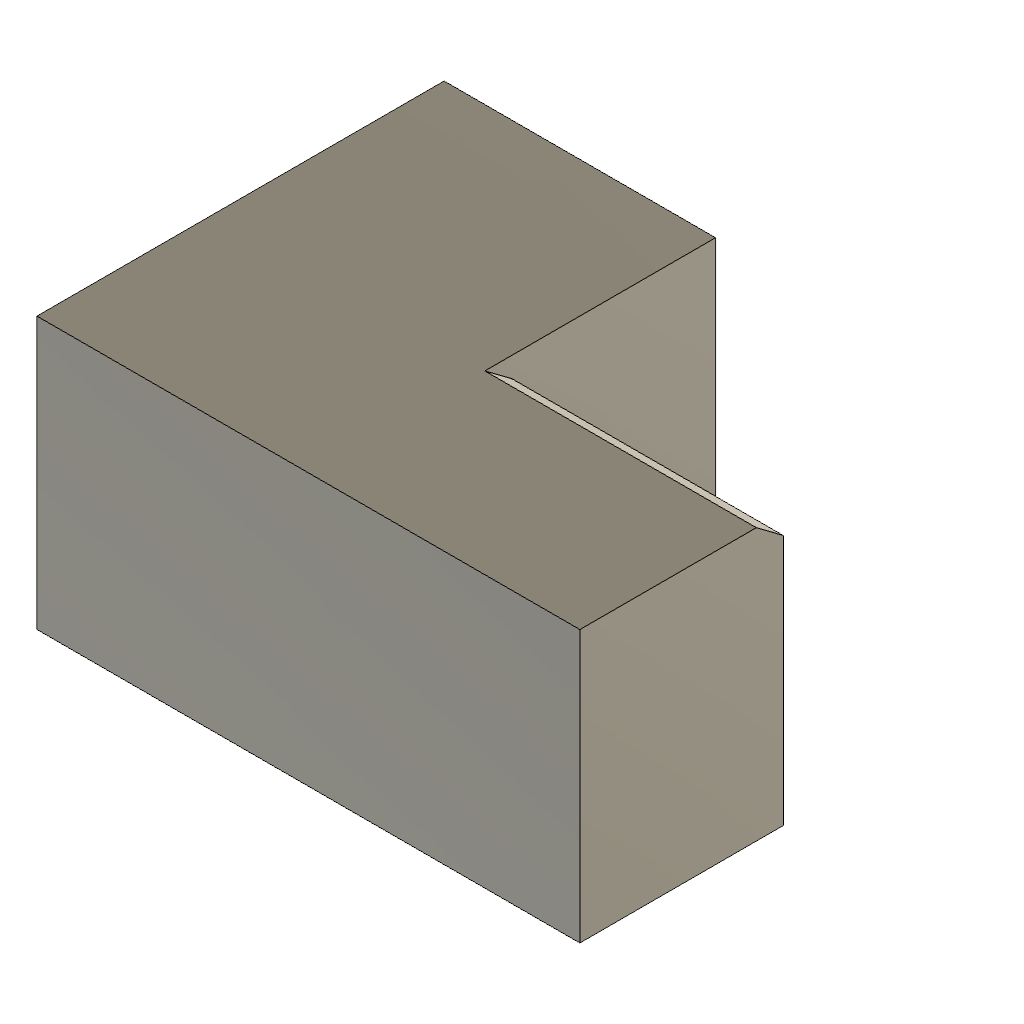
vendor_BevelStepTwo (Autodesk Fusion 360 design; units mm, degrees)
Autodesk Fusion 360 part; units mm, degrees
sketch "Step sketch" plane through (0, 0, 0) normal (0, 0, 1) x (1, 0, 0)
  line L0 (0, 0) -> (40, 0)
  line L1 (40, 0) -> (40, 15)
  line L2 (40, 15) -> (20, 15)
  line L3 (20, 15) -> (20, 30)
  line L4 (20, 30) -> (0, 30)
  line L5 (0, 30) -> (0, 0)
extrude "Step extrude" add sketch "Step sketch" along normal blind 20
chamfer "Step bevel" distance 2 distance2 1.5 1 edges at (30, 15, 20) measured on face at (6.6667, 15, 20) tangent chain off
equation "height = 20.0 mm"
